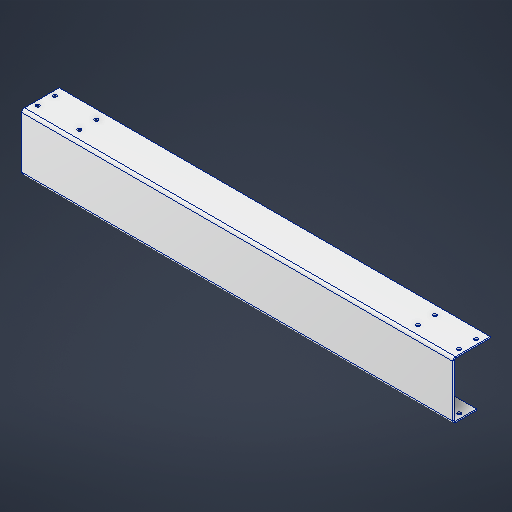
# Autodesk Inventor part: C_Bend
Saved by Autodesk Inventor 2026.2 (Build 302298010, 298A)
## iProperties
Created: 2026-07-08
Part Number: C_Bend
Material: Aluminum 6061
Document SubType Name: Sheet Metal
Designer: User
Density: 2.7 g/cm^3
Sheet Metal Rule: Default_mm
Appearance: Aluminum - Flat
Author: User
Autodesk Inventor part; units mm, degrees
ref_plane "YZ Plane" through (0, 0, 0) normal (1, 0, 0) x (0, 1, 0)
ref_plane "XZ Plane" through (0, 0, 0) normal (0, 1, 0) x (-1, 0, 0)
ref_plane "XY Plane" through (0, 0, 0) normal (0, 0, 1) x (1, 0, 0)
sketch "Sketch4" plane through (0, 0, 0) normal (0, 0, 1) x (1, 0, 0)
  line L0 (0, 0) -> (633, 0)
  line L1 (633, 0) -> (633, 84)
  line L2 (633, 84) -> (0, 84)
  line L3 (0, 84) -> (0, 0)
  dimension "d24" = 633
  dimension "d25" = 84
  measures "d24" distance of L2.end L1.end
  measures "d25" distance of L1.end L0.end
extrude "Plate2" add sketch "Sketch4" against normal blind 2
sketch "Sketch5" plane through (633, 82, 0) normal (0, 1, 0) x (-1, 0, 0)
  line L0 (633, 0) -> (0, 0)
  line L1 (0, 0) -> (0, -55)
  line L2 (0, -55) -> (633, -55)
  line L3 (633, -55) -> (633, 0)
  constraints: 6 end point, 1 horizontal, 1 perpendicular, 1 vertical
edge flange "Flange1" height 55 angle 90 thickness 2 bend radius 2 thickness toward (0, 1, 0) relief tear relief width 2 relief depth 1 edges at (316.5, 84, -2) wall of the first edge with corners at (0, 82, 0) (633, 82, 0) (633, 82, -55) (0, 82, -55)
bend "Bend1"
corner "Corner1"
sketch "Sketch6" plane through (0, 2, 0) normal (0, -1, 0) x (1, 0, 0)
  line L0 (633, 0) -> (0, 0)
  line L1 (0, 0) -> (0, -35)
  line L2 (0, -35) -> (633, -35)
  line L3 (633, -35) -> (633, 0)
  constraints: 6 end point, 1 horizontal, 1 perpendicular, 1 vertical
edge flange "Flange2" height 35 angle 90 thickness 2 bend radius 2 thickness toward (0, -1, 0) relief tear relief width 2 relief depth 1 edges at (316.5, 0, -2) wall of the first edge with corners at (633, 2, 0) (0, 2, 0) (0, 2, -35) (633, 2, -35)
bend "Bend2"
corner "Corner2"
sketch "Sketch7" plane through (0, 84, -55) normal (0, 1, 0) x (1, 0, 0)
  line L0 (633, -51) -> (0, -51) projected
  line L1 (633, 0) -> (633, -51) projected
  line L2 (0, -51) -> (0, 0) projected
  line L3 (0, -38.5) -> (6.952, -38.5)
  line L4 (0, -38.5) -> (6.952, -38.5) construction
  line L5 (6.952, -38.5) -> (68.048, -38.5)
  line L6 (633, -38.5) -> (626.048, -38.5)
  line L7 (626.048, -38.5) -> (564.952, -38.5)
  line L8 (626.048, -38.5) -> (626.048, -13.5)
  point P0 (0, -55)
  point P1 (564.952, -13.5)
  point P2 (68.048, -13.5)
  point P3 (6.952, -13.5)
  dimension "d59" = 6.952
  dimension "d61" = 61.096
  dimension "d62" = 6.952
  dimension "d63" = 61.096
  dimension "d64" = 25
  constraints: 12 end point, 5 coincident, 4 point on line, 1 collinear, 1 horizontal, 1 parallel, 1 perpendicular, 1 vertical
  measures "d59" distance of L3.start L3.end
  measures "d61" distance of L3.end L5.end
  measures "d62" distance of L6.start L6.end
  measures "d63" distance of L6.end L7.end
  measures "d64" distance of L8.start L8.end
hole "Hole2" at (68.048, 84, -16.5) at (6.952, 84, -16.5) at (626.048, 84, -16.5) at (564.952, 84, -16.5) at (564.952, 84, -41.5) at (626.048, 84, -41.5) at (68.048, 84, -41.5) at (6.952, 84, -41.5) direction (0, -1, 0) diameter 5.5 end through all
equation "\"d54\" = Thickness"
equation "\"d2\" = Thickness"
equation "\"d26\" = BendReliefWidth"
equation "\"d27\" = BendReliefDepth"
equation "\"d28\" = MinimumRemnant"
equation "\"d29\" = TransitionRadius"
equation "\"d32\" = BendRadius"
equation "\"d33\" = CornerReliefSize"
equation "\"d34\" = GapSize"
equation "\"d35\" = JacobiRadiusSize"
equation "\"d36\" = BendReliefWidth"
equation "\"d37\" = BendReliefDepth"
equation "\"d38\" = MinimumRemnant"
equation "\"d39\" = TransitionRadius"
equation "\"d42\" = BendRadius"
equation "\"d43\" = CornerReliefSize"
equation "\"d44\" = GapSize"
equation "\"d45\" = JacobiRadiusSize"
equation "\"BendRadius\" = Thickness"
equation "\"BendReliefWidth\" = Thickness"
equation "\"BendReliefDepth\" = 0.5 * Thickness"
equation "\"CornerReliefSize\" = 4 * Thickness"
equation "\"MinimumRemnant\" = 2 * Thickness"
equation "\"TransitionRadius\" = BendRadius"
equation "\"JacobiRadiusSize\" = BendRadius"
equation "\"GapSize\" = Thickness"
equation "\"Thickness\" = 2"
body "Solid1"
